Phone holder (Autodesk Fusion 360 design; units mm, degrees)
Autodesk Fusion 360 part; units mm, degrees
sketch "Sketch1" plane through (0, 0, 0) normal (0, 1, 0) x (1, 0, 0)
  line L0 (63, -35.65) -> (-63, -35.65)
  line L1 (-63, -35.65) -> (-63, 35.65)
  line L2 (-63, 35.65) -> (63, 35.65)
  line L3 (-63, -35.65) -> (63, -35.65)
  line L4 (63, -48.65) -> (-63, -48.65)
  line L5 (-63, -48.65) -> (-63, -35.65)
  line L6 (-63, -35.65) -> (-82, -35.65)
  line L7 (-82, -35.65) -> (-82, 35.65)
  line L8 (-82, 35.65) -> (-63, 35.65)
  line L9 (-63, 35.65) -> (-63, -35.65)
  line L10 (63, 35.65) -> (63, -35.65)
  line L11 (63, -35.65) -> (63, -48.65)
  line L12 (63, -35.65) -> (84, -35.65)
  line L13 (84, -35.65) -> (84, 35.65)
  line L14 (84, 35.65) -> (63, 35.65)
  line L15 (63, 35.65) -> (63, -35.65)
  dimension "d1" = 126
  dimension "d2" = 71.3
  dimension "d3" = 126
  dimension "d4" = 13
  dimension "d5" = 71.3
  dimension "d6" = 19
  dimension "d7" = 71.3
  dimension "d8" = 21
  constraint perpendicular L0 L1
  constraint parallel L0 L2
  constraint horizontal L0
  constraint horizontal L3
  constraint horizontal L4
  constraint vertical L5
  constraint horizontal L6
  constraint vertical L7
  constraint horizontal L8
  constraint vertical L9
  constraint perpendicular L4 L11
  constraint horizontal L12
  constraint vertical L13
  constraint horizontal L14
  constraint vertical L15
  measures "d1" distance of L1.end L2.end
  measures "d2" distance of L0.end L1.end
  measures "d3" distance of L0.end L0.start
  measures "d4" distance of L0.end L4.end
  measures "d5" distance of L0.end L1.end
  measures "d6" distance of L0.end L6.end
  measures "d7" distance of L0.start L2.end
  measures "d8" distance of L0.start L12.end
extrude "Extrude1" add sketch "Sketch1" along normal blind 16
sketch "Sketch2" plane through (0, 0, 48.65) normal (0, 0, 1) x (1, 0, 0)
  line L0 (-63, 0) -> (63, 0)
  line L1 (63, 0) -> (63, 16)
  line L2 (63, 16) -> (-63, 16)
  line L3 (-63, 16) -> (-63, 0)
  line L4 (0, 0) -> (0, 16)
  line L5 (0, 0) -> (0, 8)
  constraint coincident L4.start L5.start
  constraint midpoint L2 L4.end
  constraint midpoint L4 L5.end
sketch "Sketch3" plane through (0, 16, 0) normal (0, 1, 0) x (-1, 0, 0)
  line L0 (-63, 35.65) -> (-84, 35.65)
  line L1 (-84, 35.65) -> (-84, -35.65)
  line L2 (-84, -35.65) -> (82, -35.65)
  line L3 (82, -35.65) -> (82, 35.65)
  line L4 (82, 35.65) -> (63, 35.65)
  line L5 (63, 35.65) -> (63, 48.65)
  line L6 (63, 48.65) -> (-63, 48.65)
  line L7 (-63, 48.65) -> (-63, 35.65)
  line L8 (82, 37.65) -> (50, 37.65)
  line L9 (82, 37.65) -> (84, 37.65)
  line L10 (84, 37.65) -> (84, -40)
  line L11 (82, -37.65) -> (90, -37.65)
  line L12 (84, -37.65) -> (-92, -37.65)
  line L13 (-86, -35.65) -> (-86, -37.65)
  line L14 (-86, -37.65) -> (-86, 58)
  line L15 (-63, 35.65) -> (-63, 37.65)
  line L16 (-63, 37.65) -> (-98, 37.65)
  dimension "d13" = 2
  dimension "d14" = 2
  dimension "d16" = 2
  constraint perpendicular L5 L8
  constraint horizontal L9
  constraint perpendicular L2 L10
  constraint perpendicular L10 L11
  constraint coincident L10 L12.start
  constraint coincident L11 L12.start
  constraint coincident L12 L13.end
  constraint perpendicular L12 L13
  constraint coincident L0.start L7.end
  constraint vertical L15
  constraint perpendicular L14 L16
  measures "d13" distance of L8.start L9.end
  measures "d14" distance of L2.end L11.start
  measures "d16" distance of L0.start L15.end
extrude "Extrude2" add sketch "Sketch2" along normal blind 2
extrude "Extrude3" add sketch "Sketch3" against normal blind 16 contours L0 L1 L2 L3 L4 L5 L7 L8 L9 L10 L11 L12 L13 L14 L15 L16
sketch "Sketch4" plane through (0, 0, 50.65) normal (0, 0, 1) x (1, 0, 0)
  line L0 (-63, 16) -> (-63, 0)
  line L1 (-63, 0) -> (63, 0)
  line L2 (63, 0) -> (63, 16)
  line L3 (63, 16) -> (-63, 16)
  line L4 (63, 5.15) -> (-63, 5.15)
  line L5 (-63, 5.15) -> (-63, 10.85)
  line L6 (-63, 10.85) -> (63, 10.85)
  line L7 (63, 10.85) -> (63, 5.15)
  dimension "d21" = 126
  dimension "d22" = 5.7
  measures "d21" distance of L5.end L6.end
  measures "d22" distance of L4.end L5.end
extrude "Extrude4" cut sketch "Sketch4" against normal blind 13 contours L0 L2 L4 L5 L6 L7
sketch "Sketch5" plane through (86, 0, 0) normal (1, 0, 0) x (0, 0, -1)
  line L0 (37.65, 16) -> (-37.65, 16)
  line L1 (-37.65, 16) -> (-37.65, 0)
  line L2 (-37.65, 0) -> (37.65, 0)
  line L3 (37.65, 0) -> (37.65, 16)
  line L4 (-35.65, 16) -> (-35.65, 14)
  line L5 (35.65, 0) -> (35.65, 2)
  line L6 (-35.65, 14) -> (35.65, 14)
  line L7 (35.65, 14) -> (35.65, 2)
  line L8 (35.65, 2) -> (-35.65, 2)
  line L9 (-35.65, 2) -> (-35.65, 14)
  constraint coincident L0 L4.start
  constraint coincident L2 L5.start
  constraint horizontal L6
  constraint vertical L7
  constraint horizontal L8
  constraint vertical L9
extrude "Extrude5" cut sketch "Sketch5" against normal blind 168 contours L6 L7 L8 L9
extrude "Extrude6" cut sketch "Sketch1" along normal blind 20 and the other way blind -10 contours L0 L1 L2 L3 L9 L10 L15
sketch "Sketch6" plane through (-63, 0, 0) normal (-1, 0, 0) x (0, 0, 1)
  line L0 (37.65, 10.85) -> (50.65, 10.85)
  line L1 (50.65, 10.85) -> (50.65, 16)
  line L2 (50.65, 16) -> (37.65, 16)
  line L3 (37.65, 16) -> (37.65, 10.85)
extrude "Extrude7" add sketch "Sketch6" 1 faces at (-63, 3.4333, 46.3167) along normal blind 21
move_face "OffsetFaces1" offset 23 2 faces at (63, 12.5667, 41.9833) (63, 1.7167, 41.9833)
fillet "Fillet1" radius 2 4 edges at (-63, 15, 35.65) (63, 15, 35.65) (-63, 15, -35.65) (63, 15, -35.65)
sketch "Sketch7" plane through (-84, 0, 0) normal (-1, 0, 0) x (0, 0, 1)
  line L0 (50.65, 16) -> (-37.65, 16)
  line L1 (-37.65, 16) -> (-37.65, 0)
  line L2 (-37.65, 0) -> (50.65, 0)
  line L3 (50.65, 0) -> (50.65, 5.15)
  line L4 (50.65, 5.15) -> (37.65, 5.15)
  line L5 (37.65, 5.15) -> (37.65, 10.85)
  line L6 (37.65, 10.85) -> (50.65, 10.85)
  line L7 (50.65, 10.85) -> (50.65, 16)
  line L8 (50.65, 10.85) -> (50.65, 12.35)
  line L9 (50.65, 12.35) -> (37.65, 16)
  line L10 (37.65, 10.85) -> (37.65, 16)
  constraint coincident L6.end L7.start
  constraint vertical L8
  constraint coincident L0 L9.end
  constraint coincident L5.end L6.start
  constraint perpendicular L0 L10
extrude "Extrude8" cut sketch "Sketch7" against normal up to surface (170 mm away) contours L0 L7 L9
fillet "Fillet2" radius 108.5 1 edges at (1, 16, 37.65)
sketch "Sketch8" plane through (0, 0, 50.65) normal (0, 0, 1) x (1, 0, 0)
  line L0 (86, 5.15) -> (-84, 5.15)
  line L1 (-84, 5.15) -> (-84, 0)
  line L2 (-84, 0) -> (86, 0)
  line L3 (86, 0) -> (86, 5.15)
extrude "Extrude9" add sketch "Sketch8" along normal blind 20
sketch "Sketch9" plane through (-84, 0, 0) normal (-1, 0, 0) x (0, 0, 1)
  arc A0 (50.65, 12.35) -> (22.7443, 16) centre (22.7443, -92.5) ccw
  line L0 (22.7443, 16) -> (-37.65, 16)
  line L1 (-37.65, 16) -> (-37.65, 0)
  line L2 (-37.65, 0) -> (70.65, 0)
  line L3 (70.65, 0) -> (70.65, 5.15)
  line L4 (70.65, 5.15) -> (37.65, 5.15)
  line L5 (37.65, 5.15) -> (37.65, 10.85)
  line L6 (37.65, 10.85) -> (50.65, 10.85)
  line L7 (50.65, 10.85) -> (50.65, 12.35)
  line L8 (37.65, 5.15) -> (37.65, 0)
  line L9 (70.65, 2.575) -> (37.65, 0)
  line L10 (70.65, 2.575) -> (70.65, -2)
  line L11 (70.65, -2) -> (37.6254, -2)
  line L12 (37.65, 0) -> (37.6254, -2)
  constraint coincident L4.end L5.start
  constraint coincident L2 L8.end
  constraint perpendicular L2 L8
  constraint midpoint L3 L9.start
  constraint perpendicular L2 L10
  constraint perpendicular L10 L11
extrude "Extrude10" cut sketch "Sketch9" against normal blind 179 contours L2 L3 L9 L10 | L2 L10 L11 L12
fillet "Fillet3" radius 800 1 edges at (1, 0, 37.65)
fillet "Fillet4" radius 0.5 4 edges at (86, 14, 0) (86, 8, -35.65) (86, 2, 0) (86, 8, 35.65)
